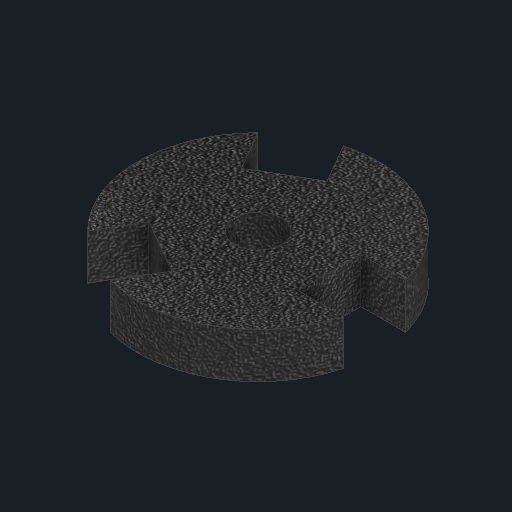
# Autodesk Inventor part: tripod_brace_hub
Saved by Autodesk Inventor 2027.1 (Build 311270010, 270A)
## iProperties
Created: 2026-11-04
Part Number: tripod_brace_hub
Material: Generic
Description: Tray brace centre hub
Document SubType Name: Modeling
Designer: Claude (from photos)
Density: 1 g/cm^3
Appearance: Black Cast
Author: alexg
Autodesk Inventor part; units mm, degrees
ref_plane "Work Plane1" through (0, -254, 0) normal (0, 1, 0) x (-1, 0, 0)
sketch "Brace hub sketch" plane through (0, -254, 0) normal (0, 1, 0) x (-1, 0, 0)
  circle A0 centre (0, 0) radius 32
  constraints: 1 centre point
extrude "Brace hub" add sketch "Brace hub sketch" along normal blind 12
ref_plane "Work Plane2" through (0, -256, 0) normal (0, 1, 0) x (-1, 0, 0)
sketch "Arm slots sketch" plane through (0, -256, 0) normal (0, 1, 0) x (-1, 0, 0)
  line L0 (-19, -8.3) -> (-34, -8.3)
  line L1 (-34, -8.3) -> (-34, 8.3)
  line L2 (-34, 8.3) -> (-19, 8.3)
  line L3 (-19, 8.3) -> (-19, -8.3)
  line L4 (16.688, -12.3045) -> (24.188, -25.2949)
  line L5 (24.188, -25.2949) -> (9.812, -33.5949)
  line L6 (9.812, -33.5949) -> (2.312, -20.6045)
  line L7 (2.312, -20.6045) -> (16.688, -12.3045)
  line L8 (2.312, 20.6045) -> (9.812, 33.5949)
  line L9 (9.812, 33.5949) -> (24.188, 25.2949)
  line L10 (24.188, 25.2949) -> (16.688, 12.3045)
  line L11 (16.688, 12.3045) -> (2.312, 20.6045)
  constraints: 24 end point
extrude "Arm slots" cut sketch "Arm slots sketch" along normal blind 16
ref_plane "Work Plane3" through (0, -256, 0) normal (0, 1, 0) x (-1, 0, 0)
sketch "Rod hole sketch" plane through (0, -256, 0) normal (0, 1, 0) x (-1, 0, 0)
  circle A0 centre (0, 0) radius 6.2
  constraints: 1 centre point
extrude "Rod hole" cut sketch "Rod hole sketch" along normal blind 16
body "Solid1"
